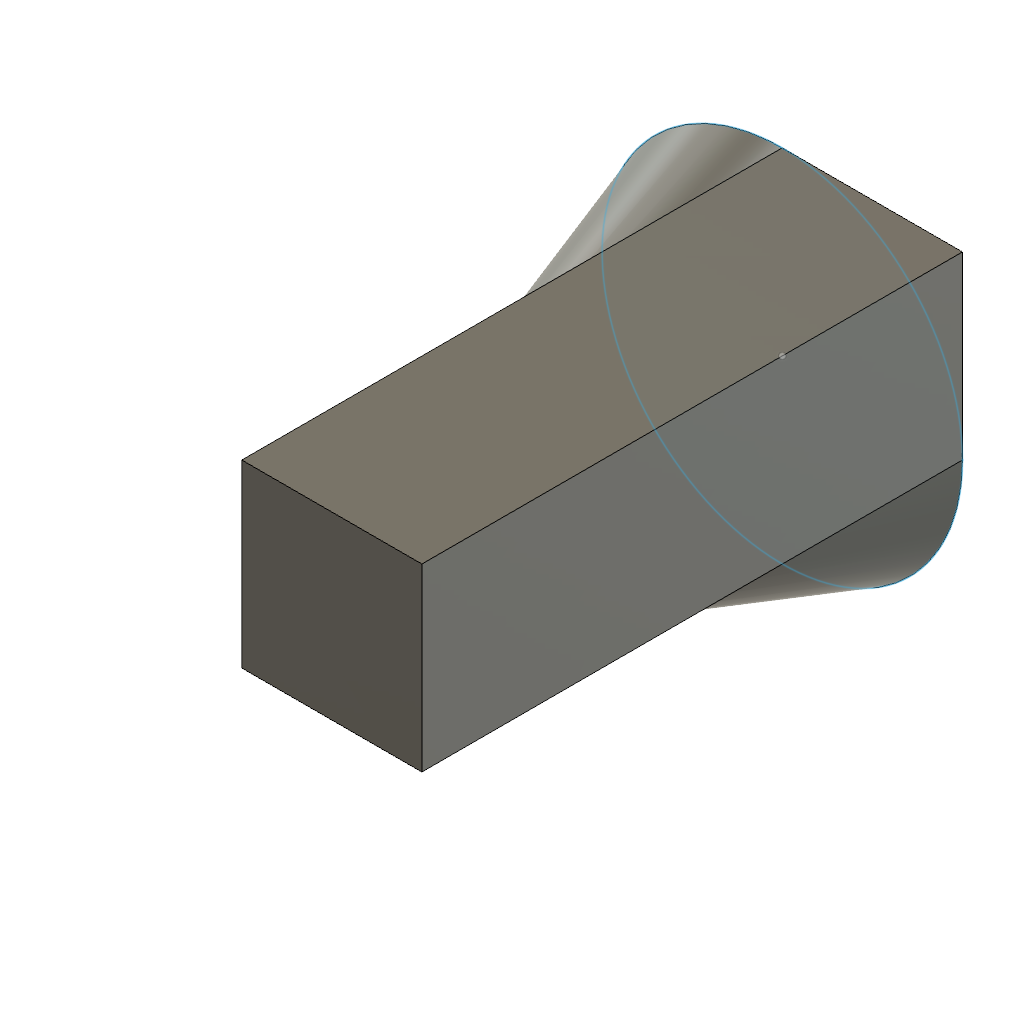
vertex_construction_sharp_end (Autodesk Fusion 360 design; units mm, degrees)
part number: 2026-10-20-22-26-13-658
Autodesk Fusion 360 part; units mm, degrees
sketch "HoldoutLoftProfile" plane through (0, 0, 0) normal (0, 0, 1) x (1, 0, 0)
  circle A0 centre (0, 0) radius 10
sketch "VertexSupportSketch" plane through (0, 0, 0) normal (0, 0, 1) x (1, 0, 0)
  line L0 (0, 0) -> (10, 0)
  line L1 (10, 0) -> (10, 10)
  line L2 (10, 10) -> (0, 10)
  line L3 (0, 10) -> (0, 0)
extrude "PointSupportExtrude" add sketch "VertexSupportSketch" along normal blind 30 makes body 1
loft "ProbeLoftPointHoldout" add profiles "HoldoutLoftProfile" section 1 section 2 point at (0, 0, 30) separate body makes body 2
named bodies: "PointSupportBody"
